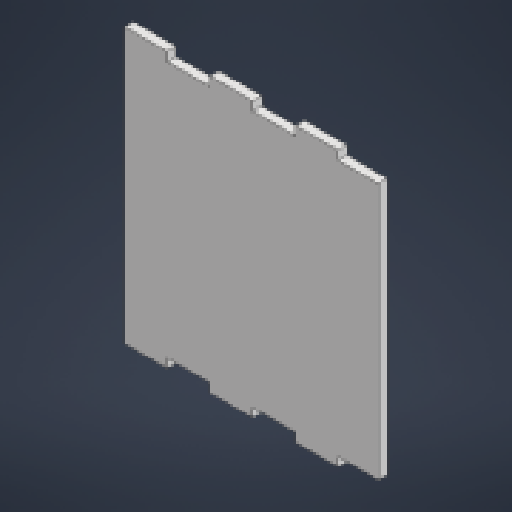
# Autodesk Inventor part: tapafrontalmdf
Saved by Autodesk Inventor 2027.1 (Build 311270010, 270A)
## iProperties
Created: 2026-10-12
Part Number: tapafrontalmdf
Material: Generic
Document SubType Name: Modeling
Designer: MineS
Density: 1 g/cm^3
Appearance: Default
Author: MineS
Autodesk Inventor part; units mm, degrees
ref_plane "YZ Plane" through (0, 0, 0) normal (1, 0, 0) x (0, 1, 0)
ref_plane "XZ Plane" through (0, 0, 0) normal (0, 1, 0) x (-1, 0, 0)
ref_plane "XY Plane" through (0, 0, 0) normal (0, 0, 1) x (1, 0, 0)
sketch "Sketch1" plane through (0, 0, 0) normal (0, 0, 1) x (1, 0, 0)
  line L0 (0, 0) -> (-15, 0) projected
  line L1 (0, 0) -> (0, 3.125) projected
  line L2 (-15, 3.125) -> (0, 3.125) projected
  line L3 (-15, 0) -> (-15, 3.125) projected
  line L4 (-30, 0) -> (-45, 0) projected
  line L5 (-30, 0) -> (-30, 3.125) projected
  line L6 (-45, 3.125) -> (-30, 3.125) projected
  line L7 (-45, 0) -> (-45, 3.125) projected
  line L8 (-60, 0) -> (-75, 0) projected
  line L9 (-60, 0) -> (-60, 3.125) projected
  line L10 (-75, 3.125) -> (-60, 3.125) projected
  line L11 (-75, 0) -> (-75, 3.125) projected
  line L12 (-75, -90) -> (-60, -90) projected
  line L13 (-75, -93.125) -> (-75, -90) projected
  line L14 (-60, -93.125) -> (-75, -93.125) projected
  line L15 (-60, -90) -> (-60, -93.125) projected
  line L16 (-45, -90) -> (-30, -90) projected
  line L17 (-45, -90) -> (-45, -93.125) projected
  line L18 (-30, -93.125) -> (-45, -93.125) projected
  line L19 (-30, -90) -> (-30, -93.125) projected
  line L20 (-15, -90) -> (0, -90) projected
  line L21 (-15, -90) -> (-15, -93.125) projected
  line L22 (0, -93.125) -> (-15, -93.125) projected
  line L23 (0, -90) -> (0, -93.125) projected
  line L24 (0, 3.125) -> (-75, 3.125)
  line L25 (-75, 3.125) -> (-75, -93.125)
  line L26 (-75, -93.125) -> (0, -93.125)
  line L27 (0, -93.125) -> (0, 3.125)
  line L28 (0, 3.125) -> (0, 0) projected
  line L29 (0, 0) -> (14.0611, 0) projected
  line L30 (14.0611, 0) -> (14.0611, 3.125) projected
  line L31 (0, 3.125) -> (14.0611, 3.125) projected
  line L32 (0, -90) -> (0, -93.125) projected
  line L33 (14.0611, -93.125) -> (0, -93.125) projected
  line L34 (14.0611, -90) -> (14.0611, -93.125) projected
  line L35 (14.0611, -90) -> (0, -90) projected
  line L36 (14.0611, 3.125) -> (-75, 3.125)
  line L37 (-75, 3.125) -> (-75, -93.125)
  line L38 (-75, -93.125) -> (14.0611, -93.125)
  line L39 (14.0611, -93.125) -> (14.0611, 3.125)
  line L40 (-60, 3.125) -> (-60, 0) projected
  line L41 (-60, 0) -> (-45, 0) projected
  line L42 (-45, 0) -> (-45, 3.125) projected
  line L43 (-60, 3.125) -> (-45, 3.125) projected
  line L44 (-60, -90) -> (-60, -93.125) projected
  line L45 (-45, -93.125) -> (-60, -93.125) projected
  line L46 (-45, -93.125) -> (-45, -90) projected
  line L47 (-45, -90) -> (-60, -90) projected
  line L48 (-30, -90) -> (-30, -93.125) projected
  line L49 (-15, -93.125) -> (-30, -93.125) projected
  line L50 (-15, -93.125) -> (-15, -90) projected
  line L51 (-15, -90) -> (-30, -90) projected
  line L52 (-15, 0) -> (-15, 3.125) projected
  line L53 (-30, 3.125) -> (-15, 3.125) projected
  line L54 (-30, 3.125) -> (-30, 0) projected
  line L55 (-30, 0) -> (-15, 0) projected
  constraints: 16 end point, 4 parallel, 2 horizontal, 2 perpendicular
extrude "Extrusion1" add sketch "Sketch1" along normal blind 3.125 contours L27 L20 L51 L16 L47 L12 L25 L8 L41 L4 L55 L0 | L0 L3 L2 L1 | L29 L39 L35 L27 | L23 L22 L21 L20 | L4 L7 L6 L5 | L19 L18 L17 L16 | L8 L11 L10 L9 | L15 L14 L13 L12
body "Solid1"
